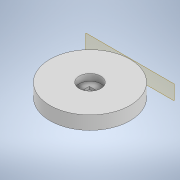
# Autodesk Inventor part: Peça2 - Encaixe do eixo
Saved by Autodesk Inventor 2022 (Build 260153000, 153)
## iProperties
Created: 2022-09-19
Part Number: Peça2 - Encaixe do eixo
Material: Genérico
Document SubType Name: Modeling
Designer: Thierry Nathan
Density: 1 g/cm^3
Appearance: Padrão
Author: Thierry Nathan
Autodesk Inventor part; units mm, degrees
ref_plane "YZ Plane" through (0, 0, 0) normal (1, 0, 0) x (0, 1, 0)
ref_plane "XZ Plane" through (0, 0, 0) normal (0, 1, 0) x (-1, 0, 0)
ref_plane "XY Plane" through (0, 0, 0) normal (0, 0, 1) x (1, 0, 0)
sketch "Esboço1" plane through (0, 0, 0) normal (0, 1, 0) x (-1, 0, 0)
  circle A0 centre (0, 0) radius 30
  dimension "d0" = 60
  constraints: 1 centre point, 1 coincident
  measures "d0" diameter of A0
extrude "Extrusão1" add sketch "Esboço1" along normal blind 10
sketch "Esboço2" plane through (0, 10, 0) normal (0, 1, 0) x (1, 0, 0)
  circle A0 centre (0, 0) radius 8.125
  dimension "d3" = 16.25
  constraints: 1 centre point, 1 coincident
  measures "d3" diameter of A0
extrude "Extrusão2" cut sketch "Esboço2" against normal blind 5
sketch "Esboço3" plane through (0, 5, 0) normal (0, 1, 0) x (1, 0, 0)
  line L0 (2.625, 2.125) -> (-2.625, 2.125)
  line L1 (-2.625, 2.125) -> (-2.625, -2.125)
  line L2 (-2.625, -2.125) -> (2.625, -2.125)
  line L3 (2.625, -2.125) -> (2.625, 2.125)
  line L4 (2.625, 2.125) -> (-2.625, -2.125) construction
  line L5 (-2.625, 2.125) -> (2.625, -2.125) construction
  point P0 (0, 0)
  dimension "d11" = 4.25
  dimension "d12" = 5.25
  constraints: 12 end point, 2 midpoint, 2 parallel, 1 horizontal, 1 perpendicular
  measures "d11" distance of L0.end L1.end
  measures "d12" distance of L1.end L2.end
extrude "Extrusão3" cut sketch "Esboço3" against normal blind 2
ref_plane "Plano de trabalho2" through (0, 5, -30) normal (0, 0, 1) x (1, 0, 0)
sketch "Esboço7" plane through (0, 5, -30) normal (0, 0, 1) x (1, 0, 0)
  line L0 (10.2, -1.7) -> (-10, -1.7)
  line L1 (-10, -1.7) -> (-10, 1.5)
  line L2 (-10, 1.5) -> (10.2, 1.5)
  line L3 (10.2, 1.5) -> (10.2, -1.7)
  line L4 (10.2, -1.7) -> (-10, 1.5) construction
  line L5 (-10, -1.7) -> (10.2, 1.5) construction
  point P0 (0, -5)
  point P1 (0.1, -0.1)
  dimension "d23" = 3.2
  dimension "d24" = 20.2
  constraints: 12 end point, 2 midpoint, 2 parallel, 1 horizontal, 1 perpendicular
  measures "d23" distance of L0.end L1.end
  measures "d24" distance of L1.end L2.end
extrude "Extrusão4" cut sketch "Esboço7" along normal blind 10
